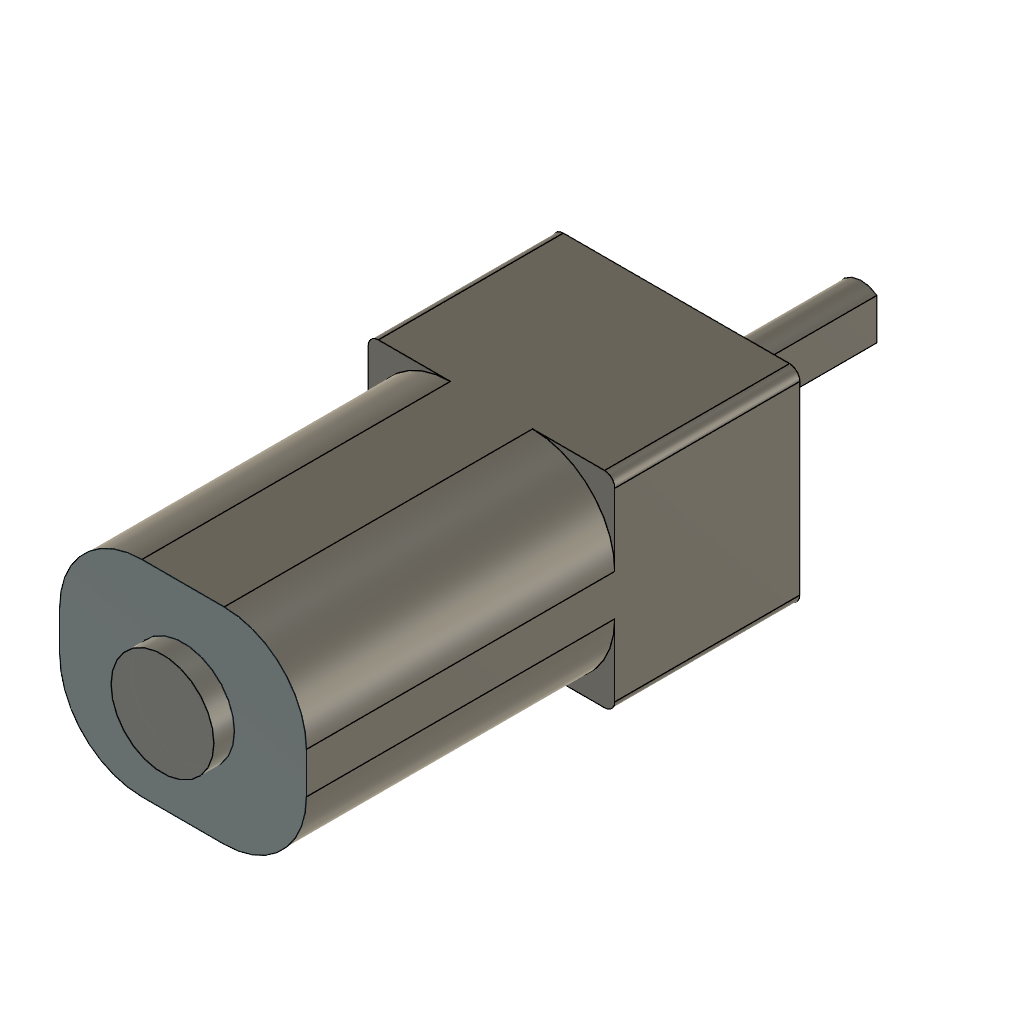
MiniMotor (Autodesk Fusion 360 design; units mm, degrees)
part number: 2026-09-30-19-01-18-395
Autodesk Fusion 360 part; units mm, degrees
sketch "Szkic1" plane through (0, 0, 0) normal (0, 1, 0) x (1, 0, 0)
  line L0 (4, 0) -> (8, 0)
  line L1 (12, -4) -> (12, -6)
  line L2 (8, -10) -> (4, -10)
  line L3 (0, -6) -> (0, -4)
  arc A0 (0, -6) -> (4, -10) centre (4, -6) ccw
  arc A1 (4, 0) -> (0, -4) centre (4, -4) ccw
  arc A2 (8, -10) -> (12, -6) centre (8, -6) ccw
  arc A3 (12, -4) -> (8, 0) centre (8, -4) ccw
  dimension "d1" = 4
  dimension "d2" = 4
  dimension "d3" = 4
  dimension "d4" = 4
  constraint horizontal L0
  constraint vertical L1
  constraint horizontal L2
  constraint vertical L3
  constraint tangent L3 A0
  constraint tangent L2 A0
  constraint tangent L0 A1
  constraint tangent L3 A1
  constraint tangent L1 A2
  constraint tangent L2 A2
  constraint tangent L0 A3
  constraint tangent L1 A3
  measures "d1" radius of A0
  measures "d2" radius of A1
  measures "d3" radius of A2
  measures "d4" radius of A3
extrude "Wyciągnięcie proste1" add sketch "Szkic1" along normal blind 15
sketch "Szkic2" plane through (0, 15, 0) normal (0, 1, 0) x (-1, 0, 0)
  arc A0 (-8, 10) -> (-12, 6) centre (-8, 6) ccw
  line L0 (-12, 6) -> (-12, 4)
  arc A1 (-12, 4) -> (-8, 0) centre (-8, 4) ccw
  line L1 (-8, 0) -> (-4, 0)
  arc A2 (-4, 0) -> (0, 4) centre (-4, 4) ccw
  line L2 (0, 4) -> (0, 6)
  arc A3 (0, 6) -> (-4, 10) centre (-4, 6) ccw
  line L3 (-4, 10) -> (-8, 10)
  line L4 (-12, 10) -> (0, 10)
  line L5 (0, 10) -> (0, 0)
  line L6 (0, 0) -> (-12, 0)
  line L7 (-12, 0) -> (-12, 10)
  constraint horizontal L4
  constraint vertical L5
  constraint horizontal L6
  constraint vertical L7
  constraint coincident L5.end L6.start
extrude "Wyciągnięcie proste2" add sketch "Szkic2" along normal blind 9
sketch "Szkic3" plane through (0, 24, 0) normal (0, 1, 0) x (-1, 0, 0)
  line L0 (-12, 0) -> (0, 0)
  line L1 (0, 0) -> (0, 10)
  line L2 (0, 10) -> (-12, 10)
  line L3 (-12, 10) -> (-12, 0)
  line L4 (-6.75, 5) -> (-6.75, 6)
  line L5 (-6.75, 5) -> (-6.75, 4)
  arc A0 (-6.75, 4) -> (-6.75, 6) centre (-6, 5) ccw
  circle A1 centre (-6, 5) radius 1.25
  constraint concentric A0 A1
extrude "Wyciągnięcie proste3" add sketch "Szkic3" along normal blind 9 contours L4 L5 A0 A1
sketch "Szkic4" plane through (0, 24, 0) normal (0, 1, 0) x (-1, 0, 0)
  arc A0 (-6.75, 4) -> (-6.75, 6) centre (-6, 5) ccw
  line L0 (-6.75, 4) -> (-6.75, 6)
  line L1 (-12, 0) -> (0, 0)
  line L2 (0, 0) -> (0, 10)
  line L3 (0, 10) -> (-12, 10)
  line L4 (-12, 10) -> (-12, 0)
  circle A1 centre (-6, 5) radius 1.5
  dimension "d11" = 3
  constraint concentric A0 A1
  measures "d11" diameter of A1
extrude "Wyciągnięcie proste4" add sketch "Szkic4" along normal blind 0.5 contours A1
sketch "Szkic5" plane through (0, 0, 0) normal (0, -1, 0) x (1, 0, 0)
  arc A0 (12, 6) -> (8, 10) centre (8, 6) ccw
  line L0 (8, 10) -> (4, 10)
  arc A1 (4, 10) -> (0, 6) centre (4, 6) ccw
  line L1 (0, 6) -> (0, 4)
  arc A2 (0, 4) -> (4, 0) centre (4, 4) ccw
  line L2 (4, 0) -> (8, 0)
  arc A3 (8, 0) -> (12, 4) centre (8, 4) ccw
  line L3 (12, 4) -> (12, 6)
  circle A4 centre (6, 5) radius 2.5
  dimension "d14" = 5
  measures "d14" diameter of A4
extrude "Wyciągnięcie proste5" add sketch "Szkic5" along normal blind 1 contours A4
sketch "Szkic6" plane through (0, 0, 0) normal (0, -1, 0) x (1, 0, 0)
  circle A0 centre (6, 5) radius 2.5
  arc A1 (12, 6) -> (8, 10) centre (8, 6) ccw
  line L0 (8, 10) -> (4, 10)
  arc A2 (4, 10) -> (0, 6) centre (4, 6) ccw
  line L1 (0, 6) -> (0, 4)
  arc A3 (0, 4) -> (4, 0) centre (4, 4) ccw
  line L2 (4, 0) -> (8, 0)
  arc A4 (8, 0) -> (12, 4) centre (8, 4) ccw
  line L3 (12, 4) -> (12, 6)
fillet "Zaokrąglenie1" radius 0.5 1 edges at (0, 19.5, 10)
fillet "Zaokrąglenie2" radius 0.5 1 edges at (12, 19.5, 10)
fillet "Zaokrąglenie3" radius 0.5 1 edges at (12, 19.5, 0)
fillet "Zaokrąglenie4" radius 0.5 1 edges at (0, 19.5, 0)
